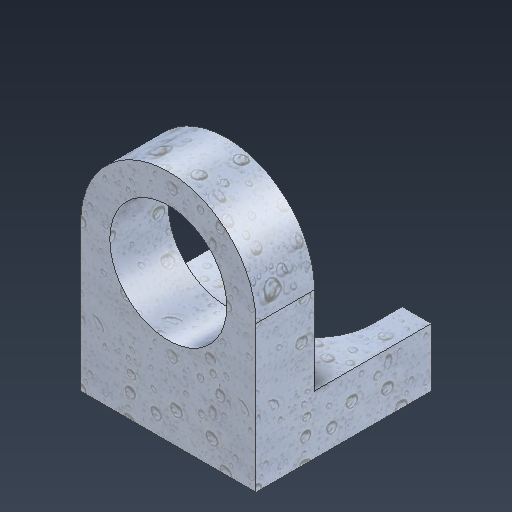
# Autodesk Inventor part: IsometricTrhee
Saved by Autodesk Inventor 2026.4 (Build 304435000, 435)
## iProperties
Created: 2026-09-06
Part Number: IsometricTrhee
Material: Generic
Document SubType Name: Modeling
Designer: YmCris
Density: 1 g/cm^3
Appearance: Default
Author: YmCris
Autodesk Inventor part; units mm, degrees
ref_plane "YZ Plane" through (0, 0, 0) normal (1, 0, 0) x (0, 1, 0)
ref_plane "XZ Plane" through (0, 0, 0) normal (0, 1, 0) x (-1, 0, 0)
sketch "Sketch1" plane through (0, 0, 0) normal (0, 1, 0) x (-1, 0, 0)
  line L0 (-15, -15) -> (15, -15)
  line L1 (15, -15) -> (15, 15)
  line L2 (15, 15) -> (-15, 15)
  line L3 (-15, 15) -> (-15, -15)
  line L4 (-15, -15) -> (15, 15) construction
  line L5 (15, -15) -> (-15, 15) construction
  point P0 (0, 0)
  dimension "d0" = 30
  dimension "d1" = 30
  constraints: 12 end point, 2 midpoint, 2 parallel, 1 horizontal, 1 perpendicular
  measures "d0" distance of L2.end L1.end
  measures "d1" distance of L1.end L0.end
extrude "Extrusion1" add sketch "Sketch1" along normal blind 10
sketch "Sketch2" plane through (0, 10, 0) normal (0, 1, 0) x (1, 0, 0)
  line L0 (0, 15) -> (0, -5) construction
  line L1 (15, 15) -> (-15, 15) construction
  line L2 (15, 15) -> (15, -5) construction
  line L3 (15, -15) -> (15, 15) construction
  line L4 (-15, -15) -> (15, -15) projected
  line L5 (-15, 15) -> (-15, -15) projected
  line L6 (15, -15) -> (-15, -15)
  line L7 (-15, -15) -> (-15, -5)
  line L8 (-15, -5) -> (15, -5)
  line L9 (15, -5) -> (15, -15)
  point P0 (0, 0)
  dimension "d7" = 20
  constraints: 12 end point, 2 parallel, 2 point on line, 1 horizontal, 1 perpendicular, 1 vertical
  measures "d7" distance of L1.start L2.end
extrude "Extrusion2" add sketch "Sketch2" along normal blind 15
ref_plane "Work Plane1" through (-15, 0, 15) normal (0, 0, 1) x (1, 0, 0)
sketch "Sketch3" plane through (-15, 0, 15) normal (0, 0, 1) x (1, 0, 0)
  arc A0 (30, 25) -> (0, 25) centre (15, 25) ccw
  arc A1 (25, 25) -> (5, 25) centre (15, 25) ccw
  line L0 (0, 25) -> (30, 25)
  point P0 (15, 0)
  constraints: 4 point on circle, 2 centre point, 2 end point, 1 coincident
extrude "Extrusion3" add sketch "Sketch3" against normal blind 10 contours L0 A1 A0
sketch "Sketch4" plane through (15, 10, 5) normal (0, 0, -1) x (-1, 0, 0)
  line L0 (5, 15) -> (25, 15) projected
  circle A0 centre (15, 15) radius 10
  point P0 (15, -10)
  dimension "d15" = 20
  constraints: 1 centre point, 1 midpoint
  measures "d15" diameter of A0
extrude "Extrusion4" cut sketch "Sketch4" against normal blind 10 contours L0 A0 picked at (13.818, 11.8833)
sketch "Sketch5" plane through (0, 10, 0) normal (0, 1, 0) x (1, 0, 0)
  line L0 (15, 15) -> (-15, 15) construction
  line L1 (0, 15) -> (0, 10) construction
  circle A0 centre (0, 10) radius 10
  point P0 (0, 0)
  dimension "d18" = 5
  dimension "d19" = 20
  constraints: 2 end point, 1 centre point, 1 coincident, 1 midpoint, 1 vertical
  measures "d18" distance of L1.start L1.end
  measures "d19" diameter of A0
extrude "Extrusion5" cut sketch "Sketch5" against normal blind 10
sketch "Sketch6" plane through (0, 10, 0) normal (0, 1, 0) x (1, 0, 0)
  line L0 (10, 15) -> (10, 10)
  line L1 (0, 15) -> (0, 10) construction
  line L2 (10, 15) -> (8.6603, 15)
  arc A0 (10, 10) -> (8.6603, 15) centre (0, 10) ccw
  line L3 (-10, 15) -> (-10, 10)
  line L4 (-10, 15) -> (-8.6603, 15)
  arc A1 (-8.6603, 15) -> (-10, 10) centre (0, 10) ccw
  point P0 (0, 0)
  constraints: 10 end point, 4 point on circle, 4 symmetric about line, 2 centre point, 2 point on line, 1 vertical, 1 other
extrude "Extrusion6" cut sketch "Sketch6" against normal blind 10 contours L0 A0 L2
sketch "Sketch7" plane through (0, 10, 0) normal (0, 1, 0) x (1, 0, 0)
  line L0 (-9.9815, 15.0312) -> (-9.9815, 10.0312)
  line L1 (-9.9815, 15.0312) -> (-8.6418, 15.0312)
  arc A0 (-8.6418, 15.0312) -> (-9.9815, 10.0312) centre (0.0185, 10.0312) ccw
  point P0 (0, 0)
  constraints: 4 end point, 2 point on circle, 1 centre point, 1 point on line
extrude "Extrusion7" cut sketch "Sketch7" against normal blind 10
body "Solid1"
